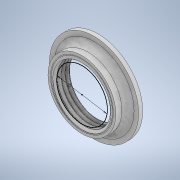
# Autodesk Inventor part: piulita_sus_buna
Saved by Autodesk Inventor 2020 (Build 240168000, 168)
## iProperties
Created: 2023-11-01
Part Number: piulita_sus_buna
Material: Generic
Document SubType Name: Modeling
Designer: user
Density: 1 g/cm^3
Appearance: Default
Author: user
Autodesk Inventor part; units mm, degrees
ref_plane "YZ Plane" through (0, 0, 0) normal (1, 0, 0) x (0, 1, 0)
ref_plane "XZ Plane" through (0, 0, 0) normal (0, 1, 0) x (-1, 0, 0)
ref_plane "XY Plane" through (0, 0, 0) normal (0, 0, 1) x (1, 0, 0)
sketch "Sketch1" plane through (0, 0, 0) normal (0, 0, 1) x (1, 0, 0)
  circle A0 centre (0, 0) radius 15.5
  circle A1 centre (0, 0) radius 16.75
  dimension "d0" = 31
  dimension "d1" = 33.5
  constraints: 2 centre point, 2 coincident
  measures "d0" diameter of A0
  measures "d1" diameter of A1
extrude "Extrusion1" add sketch "Sketch1" along normal blind 8
sketch "Sketch13" plane through (0, 0, 0) normal (0, 0, -1) x (-1, 0, 0)
  circle A0 centre (0, 0) radius 16.75 projected
  circle A1 centre (0, 0) radius 22
  dimension "d192" = 44
  constraints: 2 coincident, 1 centre point
  measures "d192" diameter of A1
extrude "Extrusion2" add sketch "Sketch13" against normal blind 2
fillet "Fillet1" radius 3 1 edges at (-16.75, 0, 2)
sketch "Sketch15" plane through (0, 0, 12) normal (-1, 0, 0) x (0, 1, 0)
  line L0 (15.5, 4) -> (15.5, 12)
  line L1 (15.5, 12) -> (15.1, 12)
  line L2 (15.1, 12) -> (15.1, 4)
  line L3 (15.1, 4) -> (15.5, 4)
  line L4 (0, -2.4) -> (0, 14.4) projected
  line L5 (-16.75, 4) -> (16.75, 4) projected
  line L6 (15.5, 4) -> (15.5, 12) projected
  point P0 (16.75, 8)
  point P1 (-16.75, 8)
  dimension "d128" = 0.4
  dimension "d129" = 0
  dimension "d173" = 8
  constraints: 8 end point
  measures "d128" distance between parallel lines of L2 L0
  measures "d129" distance between parallel lines of L6 L0
  measures "d173" distance between parallel lines of L3 L1
revolve "Revolution6" add sketch "Sketch15" angle 360 about axis through (0, 0, 12) along (0, 0, -1) separate body
sketch "Sketch18" plane through (0, 0, 8) normal (0, 0, 1) x (1, 0, 0)
  circle A0 centre (0, 0) radius 12.5
  dimension "d150" = 25
  constraints: 1 centre point, 1 coincident
  measures "d150" diameter of A0
thread "Thread9" size "M32x2" class "6H" standard "ANSI Metric M Profile" full length
sketch "Sketch22" plane through (0, 0, 8) normal (-1, 0, 0) x (0, 1, 0)
  line L0 (15.1, 0) -> (15.1, 8)
  line L1 (15.1, 8) -> (13.6171, 8)
  line L2 (13.6171, 8) -> (13.6171, 0)
  line L3 (13.6171, 0) -> (15.1, 0)
  line L4 (0, -4.2171) -> (0, 10.0362) projected
  constraints: 8 end point
revolve "Revolution9" add sketch "Sketch22" angle 360 about axis through (0, 0, 8) along (0, 0, -1) separate body
sketch "Sketch21" plane through (0, 15.1, 8) normal (1, 0, 0) x (0, 0, -1)
  line L0 (-1.1668, -0.1013) -> (-1.0001, -0.1013) construction
  line L1 (0.1666, -1.382) -> (-0.0001, -1.7021) construction
  line L2 (-2.0001, -1.7021) -> (-2.1668, -1.382) construction
  line L3 (-0.8334, -0.1013) -> (-1.0001, 0.2189) construction
  line L4 (-1.0001, 0.2189) -> (-1.1668, -0.1013) construction
  line L5 (-2.0001, -1.7021) -> (-1.8334, -1.382) construction
  line L6 (-0.8334, -0.1013) -> (-0.1668, -1.382)
  line L7 (-2.1668, -1.382) -> (-1.8334, -1.382) construction
  arc A0 (-2.1668, -1.382) -> (-2.0001, -1.4831) centre (-2.0001, -1.2952) ccw construction
  line L8 (0.1666, -1.382) -> (-0.1668, -1.382) construction
  line L9 (-2.0001, -1.7021) -> (-2.0001, -1.382) construction
  line L10 (-0.0001, -1.7021) -> (-0.0001, -1.382) construction
  line L11 (-1.0001, 0.2189) -> (-1.0001, -0.0002) construction
  line L12 (-2.0001, -1.4831) -> (-0.0001, -1.4831)
  arc A1 (-2.0001, -1.4831) -> (-1.8334, -1.382) centre (-2.0001, -1.2952) ccw
  line L13 (-0.1668, -1.382) -> (-0.0001, -1.7021) construction
  line L14 (-1.8334, -1.382) -> (-1.1668, -0.1013)
  line L15 (-0.0001, -0.0002) -> (-0.0001, 0.0177)
  line L16 (-0.0001, 0.0177) -> (-0.0001, -0.0002)
  line L17 (-0.0001, -0.0002) -> (0.0334, -0.0002)
  arc A2 (-0.1668, -1.382) -> (-0.0001, -1.4831) centre (-0.0001, -1.2952) ccw
  arc A3 (-0.0001, -1.4831) -> (0.1666, -1.382) centre (-0.0001, -1.2952) ccw construction
  arc A4 (-1.0001, -0.0002) -> (-1.1668, -0.1013) centre (-1.0001, -0.1881) ccw
  arc A5 (-0.8334, -0.1013) -> (-1.0001, -0.0002) centre (-1.0001, -0.1881) ccw
  line L18 (-1.0001, -0.0002) -> (-1.0001, -0.1013) construction
  line L19 (-1.0001, -0.1013) -> (-0.8334, -0.1013) construction
  dimension "d174" = 55
  dimension "d175" = 0.3202
  dimension "d176" = 0.3202
  dimension "Sketch21_ThreadOffset" = 0
  dimension "Sketch21_MajorRadius" = 1.4829
  dimension "d179" = 2
  dimension "Sketch21_MinorRadius" = 0
  constraints: 40 end point, 12 point on circle, 10 parallel, 8 tangent, 6 centre point, 6 collinear, 2 midpoint, 2 point on line, 1 horizontal, 1 perpendicular, 3 other
  measures "d174" angle of L6 L14
  measures "d175" distance of L3.end L0.end
  measures "d176" distance of L1.end L10.end
  measures "Sketch21_ThreadOffset" distance between parallel lines of L15 L10
  measures "Sketch21_MajorRadius" distance from line of L12 L15.start
  measures "d179" distance from line of L1.end L9
  measures "Sketch21_MinorRadius" distance edge to line of A5 L17
coil "Coil9" sketch "Sketch21" operation cut axis through (0, 0, 8) along (0, 0, -1) pitch 2.002 turns 5.994006 hand right bodies 3
equation "\"d174\" = d181"
equation "\"d175\" = 0.160083 * Sketch21_Pitch"
equation "\"d176\" = 0.160083 * Sketch21_Pitch"
equation "\"d179\" = Sketch21_Pitch"
equation "\"d13\" = 55deg"
equation "\"Sketch2_Pitch\" = 2"
equation "\"d33\" = 55deg"
equation "\"Sketch5_Pitch\" = 1.5"
equation "\"d53\" = 55deg"
equation "\"Sketch7_Pitch\" = 2"
equation "\"d73\" = 55deg"
equation "\"Sketch9_Pitch\" = 2"
equation "\"d93\" = 55deg"
equation "\"Sketch11_Pitch\" = 2"
equation "\"d117\" = 55deg"
equation "\"Sketch14_Pitch\" = 2"
equation "\"d139\" = 55deg"
equation "\"Sketch16_Pitch\" = 2"
equation "\"d160\" = 55deg"
equation "\"Sketch19_Pitch\" = 2"
equation "\"d181\" = 55deg"
equation "\"Sketch21_Pitch\" = 2"
body "Solid1"
body "Solid7"
body "Solid10"
